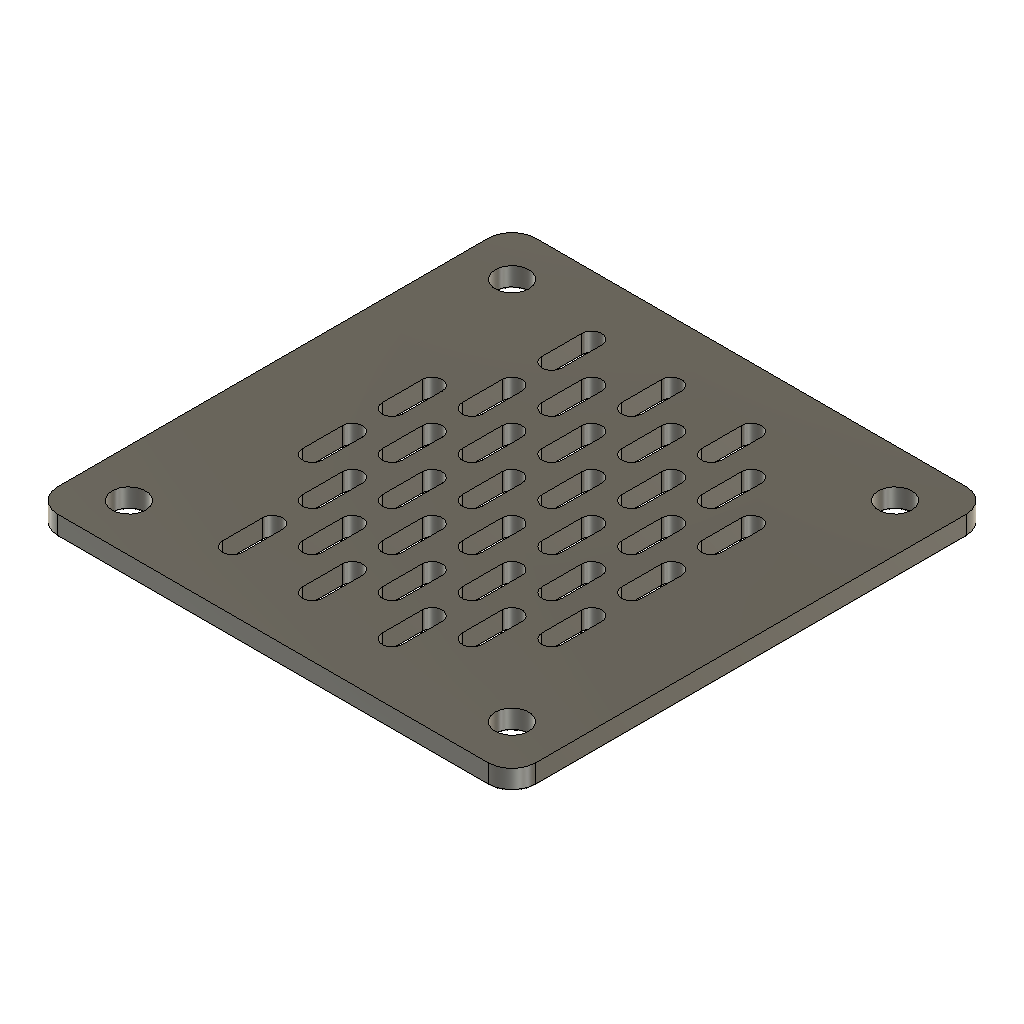
panel-standalone-v02 (Autodesk Fusion 360 design; units mm, degrees)
part number: 2026-10-27-14-47-55-175
part number: 2026-10-27-14-47-55-643
Autodesk Fusion 360 part; units mm, degrees
sketch "01 Panel blank sketch" plane through (0, 0, 0) normal (0, 0, 1) x (1, 0, 0) in component "Panel standalone"
  line L0 (0.1, 0.1) -> (119.9, 0.1)
  line L1 (119.9, 0.1) -> (119.9, 119.9)
  line L2 (119.9, 119.9) -> (0.1, 119.9)
  line L3 (0.1, 119.9) -> (0.1, 0.1)
  dimension "d31" = 0.1
  dimension "d32" = 0.1
  dimension "d33" = 119.8
  dimension "d34" = 119.8
  constraint horizontal L0
  constraint vertical L1
  constraint horizontal L2
  constraint vertical L3
  measures "d31" horizontal distance of origin L0.start
  measures "d32" vertical distance of origin L0.start
  measures "d33" horizontal distance of L0.start L0.end
  measures "d34" vertical distance of L0.end L1.end
extrude "01 Panel blank" add sketch "01 Panel blank sketch" along normal blind 5 in component "Panel standalone"
fillet "02 Rounded exterior corners" radius 6 4 edges at (0.1, 119.9, 2.5) (119.9, 119.9, 2.5) (119.9, 0.1, 2.5) (0.1, 0.1, 2.5) in component "Panel standalone"
sketch "03 A main constrained seed" plane through (0, 0, 0) normal (0, 0, 1) x (1, 0, 0) in component "Panel standalone"
  line L0 (47.5, 25) -> (47.5, 35)
  arc A0 (47.5, 35) -> (42.5, 35) centre (45, 35) ccw
  line L1 (42.5, 35) -> (42.5, 25)
  arc A1 (42.5, 25) -> (47.5, 25) centre (45, 25) ccw
  line L2 (45, 25) -> (45, 35) construction
  line L3 (45, 25) -> (55, 25) construction
  dimension "d39" = 5
  dimension "d40" = 10
  dimension "d41" = 90
  dimension "d42" = 10
  dimension "d43" = 45
  dimension "d44" = 25
  constraint tangent L0 A0
  constraint tangent A0 L1
  constraint tangent L1 A1
  constraint tangent L0 A1
  constraint parallel L0 L1
  constraint horizontal L3
  measures "d39" diameter of A0
  measures "d40" distance of A1.centre A0.centre
  measures "d41" angle of L2 L3
  measures "d42" horizontal distance of A1.centre L3.end
  measures "d43" horizontal distance of origin A1.centre
  measures "d44" vertical distance of origin A1.centre
extrude "03 A main through cut" cut sketch "03 A main constrained seed" along normal blind 5 in component "Panel standalone"
pattern_linear "03 A main lattice" count 3 spacing 20 along (1, 0, 0) count 4 spacing 20 along (0, 1, 0) of "03 A main through cut" in component "Panel standalone"
sketch "04 A end strip constrained seed" plane through (0, 0, 0) normal (0, 0, 1) x (1, 0, 0) in component "Panel standalone"
  line L0 (27.5, 45) -> (27.5, 55)
  arc A0 (27.5, 55) -> (22.5, 55) centre (25, 55) ccw
  line L1 (22.5, 55) -> (22.5, 45)
  arc A1 (22.5, 45) -> (27.5, 45) centre (25, 45) ccw
  line L2 (25, 45) -> (25, 55) construction
  line L3 (25, 45) -> (35, 45) construction
  dimension "d51" = 5
  dimension "d52" = 10
  dimension "d53" = 90
  dimension "d54" = 10
  dimension "d55" = 25
  dimension "d56" = 45
  constraint tangent L0 A0
  constraint tangent A0 L1
  constraint tangent L1 A1
  constraint tangent L0 A1
  constraint parallel L0 L1
  constraint horizontal L3
  measures "d51" diameter of A0
  measures "d52" distance of A1.centre A0.centre
  measures "d53" angle of L2 L3
  measures "d54" horizontal distance of A1.centre L3.end
  measures "d55" horizontal distance of origin A1.centre
  measures "d56" vertical distance of origin A1.centre
extrude "04 A end strip through cut" cut sketch "04 A end strip constrained seed" along normal blind 5 in component "Panel standalone"
pattern_linear "04 A end strip lattice" count 1 spacing 20 along (1, 0, 0) count 2 spacing 20 along (0, 1, 0) of "04 A end strip through cut" in component "Panel standalone"
sketch "05 B main constrained seed" plane through (0, 0, 0) normal (0, 0, 1) x (1, 0, 0) in component "Panel standalone"
  line L0 (37.5, 15) -> (37.5, 25)
  arc A0 (37.5, 25) -> (32.5, 25) centre (35, 25) ccw
  line L1 (32.5, 25) -> (32.5, 15)
  arc A1 (32.5, 15) -> (37.5, 15) centre (35, 15) ccw
  line L2 (35, 15) -> (35, 25) construction
  line L3 (35, 15) -> (45, 15) construction
  dimension "d63" = 5
  dimension "d64" = 10
  dimension "d65" = 90
  dimension "d66" = 10
  dimension "d67" = 35
  dimension "d68" = 15
  constraint tangent L0 A0
  constraint tangent A0 L1
  constraint tangent L1 A1
  constraint tangent L0 A1
  constraint parallel L0 L1
  constraint horizontal L3
  measures "d63" diameter of A0
  measures "d64" distance of A1.centre A0.centre
  measures "d65" angle of L2 L3
  measures "d66" horizontal distance of A1.centre L3.end
  measures "d67" horizontal distance of origin A1.centre
  measures "d68" vertical distance of origin A1.centre
extrude "05 B main through cut" cut sketch "05 B main constrained seed" along normal blind 5 in component "Panel standalone"
pattern_linear "05 B main lattice" count 3 spacing 20 along (1, 0, 0) count 5 spacing 20 along (0, 1, 0) of "05 B main through cut" in component "Panel standalone"
sketch "06 B end strip constrained seed" plane through (0, 0, 0) normal (0, 0, 1) x (1, 0, 0) in component "Panel standalone"
  line L0 (97.5, 35) -> (97.5, 45)
  arc A0 (97.5, 45) -> (92.5, 45) centre (95, 45) ccw
  line L1 (92.5, 45) -> (92.5, 35)
  arc A1 (92.5, 35) -> (97.5, 35) centre (95, 35) ccw
  line L2 (95, 35) -> (95, 45) construction
  line L3 (95, 35) -> (105, 35) construction
  dimension "d75" = 5
  dimension "d76" = 10
  dimension "d77" = 90
  dimension "d78" = 10
  dimension "d79" = 95
  dimension "d80" = 35
  constraint tangent L0 A0
  constraint tangent A0 L1
  constraint tangent L1 A1
  constraint tangent L0 A1
  constraint parallel L0 L1
  constraint horizontal L3
  measures "d75" diameter of A0
  measures "d76" distance of A1.centre A0.centre
  measures "d77" angle of L2 L3
  measures "d78" horizontal distance of A1.centre L3.end
  measures "d79" horizontal distance of origin A1.centre
  measures "d80" vertical distance of origin A1.centre
extrude "06 B end strip through cut" cut sketch "06 B end strip constrained seed" along normal blind 5 in component "Panel standalone"
pattern_linear "06 B end strip lattice" count 1 spacing 20 along (1, 0, 0) count 3 spacing 20 along (0, 1, 0) of "06 B end strip through cut" in component "Panel standalone"
sketch "07 Shared node clearance sketch" plane through (0, 0, 0) normal (0, 0, 1) x (1, 0, 0) in component "Panel standalone"
  circle A0 centre (12, 12) radius 4.2
  dimension "d87" = 12
  dimension "d88" = 12
  dimension "d89" = 8.4
  measures "d87" horizontal distance of origin A0.centre
  measures "d88" vertical distance of origin A0.centre
  measures "d89" diameter of A0
extrude "07 Shared node clearance" cut sketch "07 Shared node clearance sketch" along normal blind 5 in component "Panel standalone"
sketch "07 Shared node clearance sketch (1)" plane through (0, 0, 0) normal (0, 0, 1) x (1, 0, 0) in component "Panel standalone"
  circle A0 centre (12, 108) radius 4.2
  dimension "d92" = 12
  dimension "d93" = 108
  dimension "d94" = 8.4
  measures "d92" horizontal distance of origin A0.centre
  measures "d93" vertical distance of origin A0.centre
  measures "d94" diameter of A0
extrude "07 Shared node clearance (1)" cut sketch "07 Shared node clearance sketch (1)" along normal blind 5 in component "Panel standalone"
sketch "07 Shared node clearance sketch (2)" plane through (0, 0, 0) normal (0, 0, 1) x (1, 0, 0) in component "Panel standalone"
  circle A0 centre (108, 12) radius 4.2
  dimension "d97" = 108
  dimension "d98" = 12
  dimension "d99" = 8.4
  measures "d97" horizontal distance of origin A0.centre
  measures "d98" vertical distance of origin A0.centre
  measures "d99" diameter of A0
extrude "07 Shared node clearance (2)" cut sketch "07 Shared node clearance sketch (2)" along normal blind 5 in component "Panel standalone"
sketch "07 Shared node clearance sketch (3)" plane through (0, 0, 0) normal (0, 0, 1) x (1, 0, 0) in component "Panel standalone"
  circle A0 centre (108, 108) radius 4.2
  dimension "d102" = 108
  dimension "d103" = 108
  dimension "d104" = 8.4
  measures "d102" horizontal distance of origin A0.centre
  measures "d103" vertical distance of origin A0.centre
  measures "d104" diameter of A0
extrude "07 Shared node clearance (3)" cut sketch "07 Shared node clearance sketch (3)" along normal blind 5 in component "Panel standalone"
fillet "08 Rounded slot entrances and face edges" radius 0.4 2 faces at (112.4333, 61.6667, 0) (112.4333, 61.6667, 0) in component "Panel standalone"
component "Panel standalone" placed x (1, 0, 0) y (0, 1, 0) z (0, 0, 1) at (0, 0, 0)
equation "columns = 6" comment "Even integer 4..14; each cell is 20 mm"
equation "rows = 6" comment "Even integer 4..14"
equation "pitch = 20 mm" comment "Keep for dense SKADIS compatible lattice"
equation "panelWidth = columns * pitch" comment "Nominal module pitch X"
equation "panelHeight = rows * pitch" comment "Nominal module pitch Y"
equation "seamGap = 0.2 mm" comment "Physical envelope shrinks around fixed lattice"
equation "boardThickness = 5 mm" comment "Fit-test with real hooks"
equation "slotWidth = 5 mm" comment "Minimum throat width"
equation "slotHeight = 15 mm" comment "Minimum throat height"
equation "entryRadius = 0.4 mm" comment "Front slot and perimeter edge rounding"
equation "cornerRadius = 6 mm" comment "Plan-view panel corner rounding"
equation "hookClearance = 10 mm" comment "PROVISIONAL: board rear to front of extrusion"
equation "frameZ = boardThickness + hookClearance" comment "Front extrusion datum"
equation "mountInset = 12 mm" comment "Exterior node inset from outside module edge"
equation "mountBore = 8.4 mm" comment "Clearance around 8 mm metal shoulder"
equation "capDiameter = 18 mm" comment "Visible decorative mounting disk"
equation "capThickness = 2 mm" comment "Metal clamping cap / washer"
equation "seatThickness = 2 mm" comment "Printed rear bearing washer"
equation "screwDiameter = 5 mm" comment "Nominal M5 reference, threads omitted"
equation "screwClearance = 5.5 mm" comment "Cap and spacer bore"
equation "keyWidth = 4 mm" comment "Registration key corridor width"
equation "keyThickness = 2 mm" comment "Rear removable key body"
equation "keyPegDiameter = 3 mm" comment "Rear locating peg"
equation "keySocketDiameter = 3.4 mm" comment "0.2 mm radial starting fit"
equation "keyPegHeight = 0.8 mm" comment "Peg penetration"
equation "keySocketDepth = 1 mm" comment "Blind locating pocket"
equation "panelLeft = 1" comment "0 internal / 1 finished; full cell border and inset mounting"
equation "panelRight = 1" comment "0 internal / 1 finished; full cell border and inset mounting"
equation "panelBottom = 1" comment "0 internal / 1 finished; full cell border and inset mounting"
equation "panelTop = 1" comment "0 internal / 1 finished; full cell border and inset mounting"
equation "d31 = abs(( 0 mm ) + seamGap / 2)"
equation "d32 = abs(( 0 mm ) + seamGap / 2)"
equation "d33 = panelWidth - seamGap"
equation "d34 = panelHeight - seamGap"
equation "d35 = boardThickness"
equation "d38 = cornerRadius"
equation "d39 = slotWidth"
equation "d40 = slotHeight - slotWidth"
equation "d42 = pitch / 2"
equation "d43 = abs(( 0 mm ) + pitch / 4 + pitch * ( panelLeft + 1 ))"
equation "d44 = abs(( ( 0 mm ) + pitch / 2 + pitch * panelBottom ) - ( slotHeight - slotWidth ) / 2)"
equation "d45 = boardThickness"
equation "d47 = columns - panelLeft - panelRight - 1"
equation "d48 = rows - panelBottom - panelTop"
equation "d49 = pitch"
equation "d50 = pitch"
equation "d51 = slotWidth"
equation "d52 = slotHeight - slotWidth"
equation "d54 = pitch / 2"
equation "d55 = abs(( 0 mm ) + pitch / 4 + pitch * panelLeft)"
equation "d56 = abs(( ( 0 mm ) + 3 * pitch / 2 + pitch * panelBottom ) - ( slotHeight - slotWidth ) / 2)"
equation "d57 = boardThickness"
equation "d60 = rows - panelBottom - panelTop - 2"
equation "d61 = pitch"
equation "d62 = pitch"
equation "d63 = slotWidth"
equation "d64 = slotHeight - slotWidth"
equation "d66 = pitch / 2"
equation "d67 = abs(( 0 mm ) + 3 * pitch / 4 + pitch * panelLeft)"
equation "d68 = abs(( ( 0 mm ) + pitch * panelBottom ) - ( slotHeight - slotWidth ) / 2)"
equation "d69 = boardThickness"
equation "d71 = columns - panelLeft - panelRight - 1"
equation "d72 = rows + 1 - panelBottom - panelTop"
equation "d73 = pitch"
equation "d74 = pitch"
equation "d75 = slotWidth"
equation "d76 = slotHeight - slotWidth"
equation "d78 = pitch / 2"
equation "d79 = abs(( 0 mm ) + panelWidth - pitch / 4 - pitch * panelRight)"
equation "d80 = abs(( ( 0 mm ) + pitch + pitch * panelBottom ) - ( slotHeight - slotWidth ) / 2)"
equation "d81 = boardThickness"
equation "d84 = rows - 1 - panelBottom - panelTop"
equation "d85 = pitch"
equation "d86 = pitch"
equation "d87 = abs(( 0 mm ) + mountInset * panelLeft)"
equation "d88 = abs(( 0 mm ) + mountInset * panelBottom)"
equation "d89 = mountBore"
equation "d90 = boardThickness"
equation "d92 = abs(( 0 mm ) + mountInset * panelLeft)"
equation "d93 = abs(( 0 mm ) + panelHeight - mountInset * panelTop)"
equation "d94 = mountBore"
equation "d95 = boardThickness"
equation "d97 = abs(( 0 mm ) + panelWidth - mountInset * panelRight)"
equation "d98 = abs(( 0 mm ) + mountInset * panelBottom)"
equation "d99 = mountBore"
equation "d100 = boardThickness"
equation "d102 = abs(( 0 mm ) + panelWidth - mountInset * panelRight)"
equation "d103 = abs(( 0 mm ) + panelHeight - mountInset * panelTop)"
equation "d104 = mountBore"
equation "d105 = boardThickness"
equation "d108 = entryRadius"
named bodies: "Panel standalone"
